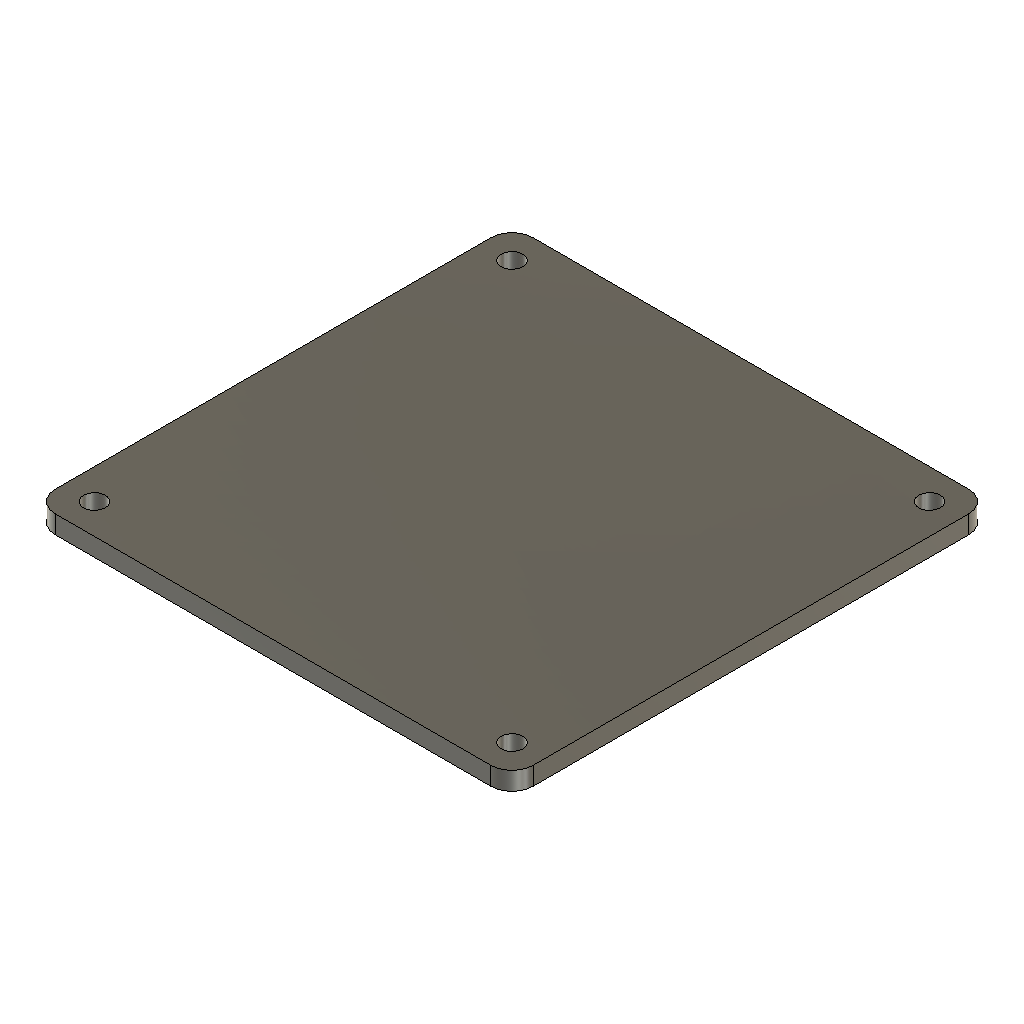
base (Autodesk Fusion 360 design; units mm, degrees)
Autodesk Fusion 360 part; units mm, degrees
sketch "Sketch1" plane through (0, 0, 0) normal (0, 0, 1) x (1, 0, 0)
  line L0 (3.5, 0) -> (75.5, 0)
  line L1 (79, 3.5) -> (79, 75.5)
  line L2 (75.5, 79) -> (3.5, 79)
  line L3 (0, 75.5) -> (0, 3.5)
  arc A0 (79, 75.5) -> (75.5, 79) centre (75.5, 75.5) ccw
  arc A1 (3.5, 79) -> (0, 75.5) centre (3.5, 75.5) ccw
  arc A2 (0, 3.5) -> (3.5, 0) centre (3.5, 3.5) ccw
  arc A3 (75.5, 0) -> (79, 3.5) centre (75.5, 3.5) ccw
  circle A4 centre (74, 5) radius 1.8
  circle A5 centre (5, 5) radius 1.8
  circle A6 centre (5, 74) radius 1.8
  circle A7 centre (74, 74) radius 1.8
  point P0 (79, 0)
  point P1 (0, 79)
  dimension "d1" = 79
  dimension "d2" = 79
  dimension "d3" = 3.5
  dimension "d4" = 3.5
  dimension "d5" = 3.5
  dimension "d6" = 3.5
  dimension "d7" = 3.6
  dimension "d8" = 5
  dimension "d9" = 5
  dimension "d10" = 3.6
  dimension "d11" = 5
  dimension "d12" = 5
  dimension "d13" = 3.6
  dimension "d14" = 5
  dimension "d15" = 5
  dimension "d16" = 3.6
  dimension "d17" = 5
  dimension "d18" = 5
  constraint horizontal L0
  constraint vertical L1
  constraint horizontal L2
  constraint vertical L3
  constraint tangent L1 A0
  constraint tangent L2 A0
  constraint coincident P1 L2
  constraint coincident P1 L3
  constraint tangent L2 A1
  constraint tangent L3 A1
  constraint coincident origin L3
  constraint coincident origin L0
  constraint tangent L3 A2
  constraint tangent L0 A2
  constraint coincident P0 L0
  constraint coincident P0 L1
  constraint tangent L0 A3
  constraint tangent L1 A3
  measures "d1" distance of origin P0
  measures "d2" distance of origin P1
  measures "d3" radius of A0
  measures "d4" radius of A1
  measures "d5" radius of A2
  measures "d6" radius of A3
  measures "d7" diameter of A4
  measures "d8" distance of L0 A4.centre
  measures "d9" distance of L1 A4.centre
  measures "d10" diameter of A5
  measures "d11" distance of L3 A5.centre
  measures "d12" distance of L0 A5.centre
  measures "d13" diameter of A6
  measures "d14" distance of L2 A6.centre
  measures "d15" distance of L3 A6.centre
  measures "d16" diameter of A7
  measures "d17" distance of L2 A7.centre
  measures "d18" distance of L1 A7.centre
extrude "Extrude1" add sketch "Sketch1" along normal blind 3
